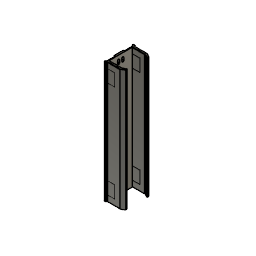
bottle_slide (Autodesk Fusion 360 design; units mm, degrees)
part number: 2026-09-13-19-58-23-760
Autodesk Fusion 360 part; units mm, degrees
sketch "Sketch1" plane through (0, 0, 0) normal (0, 0, 1) x (1, 0, 0)
  line L0 (0, -2) -> (4, -2)
  line L1 (4, -2) -> (4, 0)
  line L2 (4, 0) -> (28, 0)
  line L3 (35.0048, 3.8643) -> (35.0048, 7.8643)
  line L4 (35.0048, 7.8643) -> (28, 4)
  line L5 (0, -2) -> (0, 1)
  line L6 (0, 1) -> (2, 1)
  line L7 (2, 1) -> (2, 16.5)
  line L8 (2, 16.5) -> (0, 16.5)
  line L9 (0, 16.5) -> (0, 25.4664)
  line L10 (0, 25.4664) -> (44.4132, 25.4664) construction
  line L11 (28, 4) -> (4, 4)
  line L12 (28, 46.9328) -> (4, 46.9328)
  line L13 (35.0048, 43.0685) -> (28, 46.9328)
  line L14 (35.0048, 47.0685) -> (35.0048, 43.0685)
  line L15 (28, 50.9328) -> (35.0048, 47.0685)
  line L16 (4, 50.9328) -> (28, 50.9328)
  line L17 (4, 52.9328) -> (4, 50.9328)
  line L18 (0, 52.9328) -> (4, 52.9328)
  line L19 (0, 52.9328) -> (0, 49.9328)
  line L20 (0, 49.9328) -> (2, 49.9328)
  line L21 (2, 49.9328) -> (2, 34.4328)
  line L22 (2, 34.4328) -> (0, 34.4328)
  line L23 (0, 34.4328) -> (0, 25.4664)
  line L24 (35.0048, 3.8643) -> (28, 0)
  line L25 (4, 4) -> (4, 25.4664)
  line L26 (4, 25.4664) -> (4, 46.9328)
  dimension "d83" = 24
  dimension "d85" = 8
  dimension "d88" = 4
  dimension "d89" = 2
  dimension "d93" = 15.5
  dimension "d143" = 24
  constraint perpendicular L0 L1
  constraint perpendicular L1 L2
  constraint perpendicular L2 L3
  constraint perpendicular L0 L5
  constraint perpendicular L5 L6
  constraint perpendicular L6 L7
  constraint perpendicular L7 L8
  constraint perpendicular L8 L9
  constraint perpendicular L9 L10
  constraint horizontal L11
  constraint symmetric L0.start L10 L18.start
  constraint symmetric L0.end L10 L17.start
  constraint symmetric L1.end L10 L16.start
  constraint symmetric L2.end L10 L15.start
  constraint symmetric L3.start L10 L14.start
  constraint symmetric L3.end L10 L13.start
  constraint symmetric L4.end L10 L12.start
  constraint symmetric L5.end L10 L19.end
  constraint symmetric L6.end L10 L20.end
  constraint symmetric L7.end L10 L21.end
  constraint symmetric L8.end L10 L22.end
  constraint symmetric L9.end L10 L23.end
  constraint symmetric L10 L11.end L12.end
  constraint coincident L10 L25.end
  constraint perpendicular L10 L25
  constraint perpendicular L12 L26
  constraint parallel L4 L24
  measures "d83" distance of L1.end L2.end
  measures "d85" distance of L2.end L3.start
  measures "d88" distance of L0.start L0.end
  measures "d89" distance of L5.end L6.end
  measures "d93" distance of L6 L8
  measures "d143" distance of L4.end L11.end
extrude "Extrude6" add sketch "Sketch1" along normal blind 225
sketch "Sketch10" plane through (2, 0, 0) normal (-1, 0, 0) x (0, -1, 0)
  line L0 (-49.9328, 225) -> (-49.9328, 0)
  line L1 (-34.4328, 0) -> (-34.4328, 225)
  line L2 (-49.9328, 10) -> (-47.6828, 10)
  line L3 (-47.6828, 10) -> (-47.6828, 35)
  line L4 (-47.6828, 35) -> (-49.9328, 35)
  line L5 (-49.9328, 35) -> (-49.9328, 10)
  line L6 (-49.9328, 0) -> (-34.4328, 0)
  line L7 (-34.4328, 225) -> (-49.9328, 225)
  dimension "d128" = 2.25
  dimension "d129" = 25
  dimension "d134" = 10
  constraint horizontal L2
  constraint vertical L3
  constraint horizontal L4
  constraint vertical L5
  constraint coincident L0 L2.start
  measures "d128" distance of L2.start L2.end
  measures "d129" distance of L2.start L4.end
  measures "d134" distance of L2 L6
extrude "Extrude8" cut sketch "Sketch10" against normal blind 16 contours L0 L2 L3 L4 L5
fillet "Fillet4" radius 1 4 edges at (10, 49.9328, 10) (10, 47.6828, 10) (10, 47.6828, 35) (10, 49.9328, 35)
ref_plane "WorkPlane7" through (17.5024, 25.4664, 112.5) normal (0, 0, 1) x (1, 0, 0)
mirror "Mirror3" about plane through (17.5024, 25.4664, 112.5) normal (0, 0, 1) of "Extrude8", "Fillet4"
ref_plane "WorkPlane8" through (16, 25.4664, 112.5) normal (0, -1, 0) x (1, 0, 0)
mirror "Mirror4" about plane through (16, 25.4664, 112.5) normal (0, -1, 0) of "Extrude8", "Fillet4", "Mirror3"
fillet "Fillet2" radius 5 2 edges at (28, 46.9328, 112.5) (28, 4, 112.5)
fillet "Fillet2" radius 5 1 edges at (28, 50.9328, 112.5)
fillet "Fillet2" radius 1 2 edges at (4, 0, 112.5) (4, 50.9328, 112.5)
fillet "Fillet2" radius 1 2 edges at (4, 52.9328, 112.5) (4, -2, 112.5)
fillet "Fillet2" radius 1 6 edges at (0, 52.9328, 112.5) (0, 49.9328, 112.5) (0, 34.4328, 112.5) (0, 16.5, 112.5) (0, 1, 112.5) (0, -2, 112.5)
fillet "Fillet3" radius 1 3 edges at (35.0048, 7.8643, 112.5) (35.0048, 43.0685, 112.5) (35.0048, 47.0685, 112.5)
chamfer "Chamfer1" distance 0.5 angle 45 72 edges at (15.3561, 4, 0) (27.9593, 4.158, 0) (31.3246, 5.8341, 0) (34.5132, 7.0317, 0) (35.0048, 5.0175, 0) (1.5, 49.9328, 0) (0.2929, 50.2257, 0) (0, 51.4328, 0) (0.2929, 52.6399, 0) (2, 52.9328, 0) (3.7071, 52.6399, 0) (4.2929, 51.2257, 0) (15.8561, 50.9328, 0) (27.9593, 50.7748, 0) (31.8077, 48.8322, 0) (34.8659, 46.9865, 0) (35.0048, 45.6202, 0) (34.5132, 43.9011, 0) (31.3246, 45.0987, 0) (27.9593, 46.7748, 0) (15.3561, 46.9328, 0) (16.5, 0, 0) (4.2929, -0.2929, 0) (3.7071, -1.7071, 0) (2, -2, 0) (0.2929, -1.7071, 0) (0, -0.5, 0) (0.2929, 0.7071, 0) (1.5, 1, 0) (2, 42.1828, 0) (0.2929, 34.1399, 0) (1.5, 34.4328, 0) (1.5, 16.5, 0) (0.2929, 16.7929, 0) (0, 25.4664, 0) (2, 8.75, 0) (15.8561, 50.9328, 225) (27.9593, 50.7748, 225) (31.8077, 48.8322, 225) (34.8659, 46.9865, 225) (35.0048, 45.6202, 225) (34.5132, 43.9011, 225) (31.3246, 45.0987, 225) (27.9593, 46.7748, 225) (15.3561, 46.9328, 225) (1.5, 49.9328, 225) (0.2929, 50.2257, 225) (0, 51.4328, 225) (0.2929, 52.6399, 225) (2, 52.9328, 225) (3.7071, 52.6399, 225) (4.2929, 51.2257, 225) (15.3561, 4, 225) (27.9593, 4.158, 225) (31.3246, 5.8341, 225) (34.5132, 7.0317, 225) (35.0048, 5.0175, 225) (16.5, 0, 225) (4.2929, -0.2929, 225) (3.7071, -1.7071, 225) (2, -2, 225) (0.2929, -1.7071, 225) (0, -0.5, 225) (0.2929, 0.7071, 225) (1.5, 1, 225) (2, 42.1828, 225) (0.2929, 34.1399, 225) (0, 25.4664, 225) (0.2929, 16.7929, 225) (1.5, 16.5, 225) (1.5, 34.4328, 225) (2, 8.75, 225) tangent chain off
sketch "Sketch9" plane through (0, 0, 0) normal (-1, 0, 0) x (0, -1, 0)
  line L0 (-17.5, 224.5) -> (-33.4328, 224.5)
  line L1 (-33.4328, 224.5) -> (-33.4328, 0.5)
  line L2 (-33.4328, 0.5) -> (-17.5, 0.5)
  line L3 (-17.5, 0.5) -> (-17.5, 224.5)
  line L4 (-21, 5) -> (-22, 5)
  line L5 (-23.5, 6.5) -> (-23.5, 11.5)
  line L6 (-22, 13) -> (-21, 13)
  line L7 (-19.5, 11.5) -> (-19.5, 6.5)
  arc A0 (-21, 5) -> (-19.5, 6.5) centre (-21, 6.5) ccw
  arc A1 (-23.5, 6.5) -> (-22, 5) centre (-22, 6.5) ccw
  arc A2 (-22, 13) -> (-23.5, 11.5) centre (-22, 11.5) ccw
  arc A3 (-19.5, 11.5) -> (-21, 13) centre (-21, 11.5) ccw
  point P0 (-19.5, 5)
  point P1 (-23.5, 5)
  point P2 (-19.5, 13)
  dimension "d117" = 4
  dimension "d118" = 8
  dimension "d119" = 1.5
  dimension "d144" = 2
  constraint horizontal L4
  constraint vertical L5
  constraint horizontal L6
  constraint vertical L7
  constraint coincident P0 L4
  constraint coincident P0 L7
  constraint tangent L4 A0
  constraint tangent L7 A0
  constraint coincident P1 L4
  constraint coincident P1 L5
  constraint tangent L4 A1
  constraint tangent L5 A1
  constraint equal A0 A1
  constraint tangent L5 A2
  constraint tangent L6 A2
  constraint equal A0 A2
  constraint coincident P2 L6
  constraint coincident P2 L7
  constraint tangent L6 A3
  constraint tangent L7 A3
  constraint equal A0 A3
  measures "d117" distance of P0 P1
  measures "d118" distance of P0 P2
  measures "d119" radius of A0
  measures "d144" distance of L3 L7
extrude "Extrude7" cut sketch "Sketch9" against normal up to surface (4 mm away) contours L4 L5 L6 L7 A0 A1 A2 A3
pattern_linear "R-Pattern4" count 12 spacing 18.6364 along (0, 0, 1) count 2 spacing 8 along (0, 1, 0) of "Extrude7"
equation "d143 = d83"
